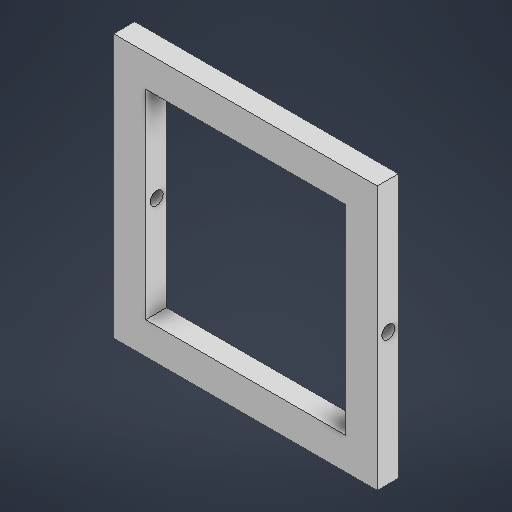
# Autodesk Inventor part: InnerFrameY
Saved by Autodesk Inventor 2026.2 (Build 302298010, 298A)
## iProperties
Created: 2026-03-09
Part Number: InnerFrameY
Material: Generic
Document SubType Name: Modeling
Designer: User
Density: 1 g/cm^3
Appearance: Default
Author: User
Autodesk Inventor part; units mm, degrees
ref_plane "YZ Plane" through (0, 0, 0) normal (1, 0, 0) x (0, 1, 0)
ref_plane "XZ Plane" through (0, 0, 0) normal (0, 1, 0) x (-1, 0, 0)
ref_plane "XY Plane" through (0, 0, 0) normal (0, 0, 1) x (1, 0, 0)
sketch "Sketch1" plane through (0, 0, 0) normal (0, 0, 1) x (1, 0, 0)
  line L0 (-45.2559, 27.1322) -> (54.7441, 27.1322)
  line L1 (54.7441, 27.1322) -> (54.7441, -72.8678)
  line L2 (54.7441, -72.8678) -> (-45.2559, -72.8678)
  line L3 (-45.2559, -72.8678) -> (-45.2559, 27.1322)
  line L4 (42.6321, 15.0202) -> (-33.1438, 15.0202)
  line L5 (-33.1438, 15.0202) -> (-33.1438, -60.7558)
  line L6 (-33.1438, -60.7558) -> (42.6321, -60.7558)
  line L7 (42.6321, -60.7558) -> (42.6321, 15.0202)
  point P0 (0, 0)
  dimension "d0" = 100
  dimension "d1" = 100
  constraints: 16 end point, 4 parallel, 2 perpendicular, 1 horizontal, 3 other
  measures "d0" distance of L0.start L0.end
  measures "d1" distance of L0.end L1.end
extrude "Extrusion1" add sketch "Sketch1" along normal blind 8
sketch "Sketch2" plane through (-45.2559, -72.8678, 0) normal (-1, 0, 0) x (0, 0, 1)
  circle A0 centre (3.7968, 50) radius 2.5
  line L0 (0, 100) -> (8, 100) projected
  point P0 (0, 72.8678)
  point P1 (4, 100)
  dimension "d4" = 5
  dimension "d5" = 50
  constraints: 1 centre point, 1 midpoint
  measures "d4" diameter of A0
  measures "d5" vertical distance of point (4, 100) A0.centre
extrude "Extrusion2" cut sketch "Sketch2" against normal through all
body "Solid1"
